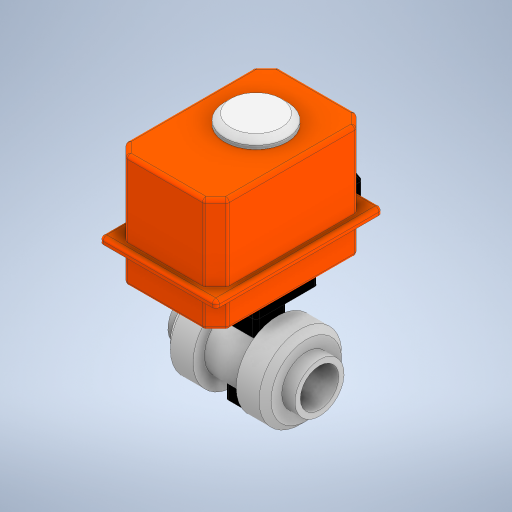
# Autodesk Inventor part: СДР 032 Электроклапан mm
Saved by Autodesk Inventor 2024.2 (Build 282272000, 272)
## iProperties
Created: 2024-04-05
Part Number: СДР 032 Электроклапан mm
Material: Generic
Document SubType Name: Modeling
Designer: pokla
Density: 1 g/cm^3
Appearance: Default
Author: pokla
Autodesk Inventor part; units mm, degrees
ref_plane "YZ Plane" through (0, 0, 0) normal (1, 0, 0) x (0, 1, 0)
ref_plane "XZ Plane" through (0, 0, 0) normal (0, 1, 0) x (-1, 0, 0)
ref_plane "XY Plane" through (0, 0, 0) normal (0, 0, 1) x (1, 0, 0)
sketch "Sketch1" plane through (0, 0, 0) normal (0, 1, 0) x (-1, 0, 0)
  line L0 (42.5, -51) -> (-42.5, -51)
  line L1 (-42.5, -51) -> (-42.5, 76)
  line L2 (-42.5, 76) -> (42.5, 76)
  line L3 (42.5, 76) -> (42.5, -51)
  line L4 (-48.5, -57) -> (48.5, -57)
  line L5 (48.5, -57) -> (48.5, 82)
  line L6 (48.5, 82) -> (-48.5, 82)
  line L7 (-48.5, 82) -> (-48.5, -57)
  point P0 (0, 0)
  point P1 (0, -51)
  dimension "d0" = 85
  dimension "d1" = 127
  dimension "d5" = 51
  dimension "d6" = 6
  constraints: 16 end point, 4 parallel, 2 perpendicular, 1 horizontal, 1 midpoint, 1 vertical alignment, 3 other
  measures "d0" distance of L1.end L2.end
  measures "d1" distance of L0.end L1.end
  measures "d5" distance of point (0, 0) point (0, -51)
  measures "d6" distance between parallel lines of L0 L4
extrude "Extrusion1" add sketch "Sketch1" along normal mid plane 5.5 contours L0 L1 L2 L3 | L7 L6 L5 L4
sketch "Sketch2" plane through (0, 0, 0) normal (0, 1, 0) x (-1, 0, 0)
  line L0 (48.5, -57) -> (48.5, 82) projected
  line L1 (48.5, 82) -> (-48.5, 82) projected
  line L2 (-48.5, 82) -> (-48.5, -57) projected
  line L3 (-48.5, -57) -> (48.5, -57) projected
  line L4 (42.5, -51) -> (42.5, 76)
  line L5 (42.5, 76) -> (-42.5, 76)
  line L6 (-42.5, 76) -> (-42.5, -51)
  line L7 (-42.5, -51) -> (42.5, -51)
  point P0 (0, 0)
  dimension "d9" = 6
  constraints: 8 end point, 3 other
  measures "d9" distance between parallel lines of L3 L7
extrude "Extrusion2" add sketch "Sketch2" along normal blind 66 and the other way blind 29 contours L7 L6 L5 L4
sketch "Sketch3" plane through (0, 0, 0) normal (0, 1, 0) x (-1, 0, 0)
  circle A0 centre (0, 0) radius 26
  line L0 (48.5, -57) -> (-48.5, -57) projected
  line L1 (42.5, 76) -> (-42.5, 76) projected
  line L2 (-42.5, 76) -> (-42.5, -51) projected
  line L3 (-42.5, -51) -> (42.5, -51) projected
  line L4 (42.5, -51) -> (42.5, 76) projected
  point P0 (0, 0)
  point P1 (0, -57)
  point P2 (0, -51)
  dimension "d14" = 52
  dimension "d16" = 51
  constraints: 2 midpoint, 1 centre point, 1 coincident
  measures "d14" diameter of A0
  measures "d16" distance of A0.centre point (0, -51)
extrude "Extrusion3" add sketch "Sketch3" along normal blind 74 and the other way blind 0.5 contours A0
sketch "Sketch4" plane through (0, 0, 0) normal (0, 1, 0) x (-1, 0, 0)
  line L0 (27, -27) -> (-27, -27)
  line L1 (-27, -27) -> (-27, 27)
  line L2 (-27, 27) -> (27, 27)
  line L3 (27, 27) -> (27, -27)
  circle A0 centre (0, 0) radius 26 projected
  line L4 (42.5, 76) -> (-42.5, 76) projected
  line L5 (-42.5, 76) -> (-42.5, -51) projected
  line L6 (-42.5, -51) -> (42.5, -51) projected
  line L7 (42.5, -51) -> (42.5, 76) projected
  point P0 (0, 0)
  point P1 (0, -27)
  point P2 (0, -51)
  dimension "d21" = 54
  dimension "d22" = 54
  dimension "d23" = 24
  constraints: 8 end point, 2 midpoint, 2 parallel, 1 horizontal, 1 perpendicular, 1 vertical alignment
  measures "d21" distance of L1.end L2.end
  measures "d22" distance of L0.end L1.end
  measures "d23" distance of point (0, -27) point (0, -51)
extrude "Extrusion4" add sketch "Sketch4" against normal blind 39 contours L0 L1 L2 L3 | A0
sketch "Sketch5" plane through (0, 0, 0) normal (0, 1, 0) x (-1, 0, 0)
  line L0 (-27, 27) -> (27, 27) projected
  line L1 (27, 27) -> (27, -27) projected
  line L2 (27, -27) -> (-27, -27) projected
  line L3 (-27, -27) -> (-27, 27) projected
  line L4 (-26, -26) -> (26, -26)
  line L5 (26, -26) -> (26, 26)
  line L6 (26, 26) -> (-26, 26)
  line L7 (-26, 26) -> (-26, -26)
  point P0 (0, 0)
  dimension "d26" = 1
  constraints: 8 end point, 3 other
  measures "d26" distance between parallel lines of L2 L4
extrude "Extrusion5" add sketch "Sketch5" against normal blind 50 contours L7 L6 L5 L4
sketch "Sketch6" plane through (0, 0, 0) normal (0, 1, 0) x (-1, 0, 0)
  line L0 (26, 26) -> (26, -26) projected
  line L1 (26, -26) -> (-26, -26) projected
  line L2 (-26, -26) -> (-26, 26) projected
  line L3 (-26, 26) -> (26, 26) projected
  line L4 (-13, -13) -> (13, -13)
  line L5 (13, -13) -> (13, 13)
  line L6 (13, 13) -> (-13, 13)
  line L7 (-13, 13) -> (-13, -13)
  point P0 (0, 0)
  dimension "d29" = 13
  constraints: 8 end point, 3 other
  measures "d29" distance between parallel lines of L1 L4
extrude "Extrusion6" add sketch "Sketch6" against normal blind 132 contours L7 L6 L5 L4
sketch "Sketch7" plane through (0, 0, 0) normal (1, 0, 0) x (0, 1, 0)
  line L0 (-50, -13) -> (-50, 13) projected
  line L1 (-50, -13) -> (-132, -13) projected
  line L2 (-132, 13) -> (-132, -13) projected
  line L3 (-50, 13) -> (-132, 13) projected
  circle A0 centre (-98, 0) radius 25
  point P0 (0, 0)
  point P1 (-50, 0)
  dimension "d32" = 50
  dimension "d33" = 48
  constraints: 1 centre point, 1 horizontal alignment, 1 midpoint
  measures "d32" diameter of A0
  measures "d33" distance of point (-50, 0) A0.centre
extrude "Extrusion7" add sketch "Sketch7" along normal mid plane 36 contours A0 L1 | L1 A0 L3 | L3 A0
sketch "Sketch8" plane through (0, 0, 0) normal (1, 0, 0) x (0, 1, 0)
  circle A0 centre (-98, 0) radius 25 projected
  circle A1 centre (-98, 0) radius 16
  circle A2 centre (-98, 0) radius 20.5
  point P0 (0, 0)
  dimension "d36" = 32
  dimension "d37" = 41
  constraints: 2 centre point, 2 coincident
  measures "d36" diameter of A1
  measures "d37" diameter of A2
extrude "Extrusion8" add sketch "Sketch8" along normal mid plane 106 contours A2
sketch "Sketch9" plane through (-18, -98, 0) normal (-1, 0, 0) x (0, 0, 1)
  circle A0 centre (0, 0) radius 16 projected
  circle A1 centre (0, 0) radius 34.5
  point P0 (0, 98)
  dimension "d40" = 69
  constraints: 1 centre point, 1 coincident
  measures "d40" diameter of A1
extrude "Extrusion9" add sketch "Sketch9" along normal blind 24
chamfer "Chamfer1" distance 5 angle 45 1 edges at (-42, -98, -34.5)
mirror "Mirror1" about plane through (0, 0, 0) normal (1, 0, 0) of "Extrusion9", "Chamfer1"
sketch "Sketch10" plane through (0, 0, 0) normal (0, 0, 1) x (1, 0, 0)
  line L0 (-48.5, -2.75) -> (48.5, -2.75) projected
  line L1 (42.5, -2.75) -> (-42.5, -2.75) projected
  line L2 (42.5, -29) -> (42.5, -2.75) projected
  line L3 (-42.5, -29) -> (42.5, -29) projected
  line L4 (-42.5, -29) -> (-42.5, -2.75) projected
  line L5 (12, -2.75) -> (12, -14.75)
  arc A0 (-12, -14.75) -> (12, -14.75) centre (0, -14.75) ccw
  line L6 (-12, -14.75) -> (-12, -2.75)
  point P0 (0, 0)
  point P1 (0, -26.75)
  point P2 (0, -2.75)
  dimension "d46" = 24
  dimension "d47" = 24
  constraints: 4 end point, 3 point on circle, 2 perpendicular, 2 point on line, 2 tangent, 1 centre point, 1 midpoint, 1 vertical alignment
  measures "d46" distance between parallel lines of L6 L5
  measures "d47" distance of point (0, -2.75) point (0, -26.75)
extrude "Extrusion10" add sketch "Sketch10" against normal blind 56 contours L0 L5 A0 L6
sketch "Sketch11" plane through (0, 0, 0) normal (0, 0, 1) x (1, 0, 0)
  line L0 (12, -2.75) -> (12, -14.75) projected
  arc A0 (-12, -14.75) -> (12, -14.75) centre (0, -14.75) ccw projected
  line L1 (-12, -14.75) -> (-12, -2.75) projected
  line L2 (12, -2.75) -> (-12, -2.75) projected
  line L3 (0, -2.6256) -> (10.5, -8.6878)
  line L4 (10.5, -8.6878) -> (10.5, -20.8122)
  line L5 (10.5, -20.8122) -> (0, -26.8744)
  line L6 (0, -26.8744) -> (-10.5, -20.8122)
  line L7 (-10.5, -20.8122) -> (-10.5, -8.6878)
  line L8 (-10.5, -8.6878) -> (0, -2.6256)
  point P0 (0, 0)
  dimension "d50" = 21
  constraints: 12 end point, 1 coincident, 1 parallel, 13 other
  measures "d50" distance between parallel lines of L7 L4
extrude "Extrusion11" add sketch "Sketch11" against normal blind 82 contours L3 L4 A0 L5 L6 L7 L8 L2 | L2 L8 L3 | L4 L5 A0 | L5 L6 A0 | A0 L6 L7
chamfer "Chamfer2" distance 5 angle 45 6 edges at (-5.25, -5.6567, -82) (5.25, -5.6567, -82) (10.5, -14.75, -82) (5.25, -23.8433, -82) (-5.25, -23.8433, -82) (-10.5, -14.75, -82)
chamfer "Chamfer3" distance 5 angle 45 1 edges at (26, 74, 0)
sketch "Sketch12" plane through (0, 0, 0) normal (0, 1, 0) x (-1, 0, 0)
  line L0 (-27, 27) -> (-27, -27) projected
  line L1 (-27, -27) -> (27, -27) projected
  line L2 (27, -27) -> (27, 27) projected
  line L3 (27, 27) -> (-27, 27) projected
  line L4 (-42.5, 76) -> (42.5, 76) projected
  line L5 (42.5, 76) -> (42.5, -51) projected
  line L6 (42.5, -51) -> (-42.5, -51) projected
  line L7 (-42.5, -51) -> (-42.5, 76) projected
  circle A0 centre (6.5, 43) radius 4
  circle A1 centre (6.5, 43) radius 2.5
  point P0 (0, 0)
  dimension "d59" = 8
  dimension "d60" = 36
  dimension "d61" = 33
  dimension "d62" = 5
  constraints: 2 centre point, 1 coincident
  measures "d59" diameter of A0
  measures "d60" distance from line of L5 A0.centre
  measures "d61" distance from line of L4 A0.centre
  measures "d62" diameter of A1
extrude "Extrusion12" add sketch "Sketch12" against normal blind 39 contours A0
chamfer "Chamfer4" distance 10 angle 45 8 edges at (42.5, 34.375, 76) (42.5, 34.375, -51) (42.5, -15.875, -51) (42.5, -15.875, 76) (-42.5, -15.875, -51) (-42.5, 34.375, -51) (-42.5, -15.875, 76) (-42.5, 34.375, 76)
fillet "Fillet1" radius 3 32 edges at (-42.5, 66, 12.5) (0, 66, -51) (0, 66, 76) (42.5, 66, 12.5) (-37.5, 66, 71) (37.5, 66, 71) (37.5, 66, -46) (-37.5, 66, -46) (-37.5, -29, 71) (0, -29, 76) (37.5, -29, 71) (42.5, -29, 12.5) (37.5, -29, -46) (0, -29, -51) (-37.5, -29, -46) (-42.5, -29, 12.5) (32.5, 34.375, -51) (42.5, 34.375, -41) (32.5, -15.875, -51) (42.5, -15.875, -41) (-32.5, 34.375, -51) (-42.5, 34.375, -41) (-42.5, -15.875, -41) (-32.5, -15.875, -51) (-32.5, 34.375, 76) (-42.5, 34.375, 66) (-32.5, -15.875, 76) (-42.5, -15.875, 66) (42.5, 34.375, 66) (32.5, 34.375, 76) (42.5, -15.875, 66) (32.5, -15.875, 76)
fillet "Fillet2" radius 3 8 edges at (-48.5, 0, -57) (0, 2.75, -57) (-48.5, 2.75, 12.5) (48.5, 0, -57) (48.5, 2.75, 12.5) (48.5, 0, 82) (0, 2.75, 82) (-48.5, 0, 82)
fillet "Fillet3" radius 3 16 edges at (27, -34, -27) (26, -44.5, -26) (-27, -34, -27) (-26, -44.5, -26) (-27, -34, 27) (-26, -44.5, 26) (27, -34, 27) (26, -44.5, 26) (13, -63.3229, 13) (13, -63.3229, -13) (-13, -63.3229, -13) (-13, -63.3229, 13) (-13, -125.6771, 13) (13, -125.6771, 13) (13, -125.6771, -13) (-13, -125.6771, -13)
body "Solid1"
